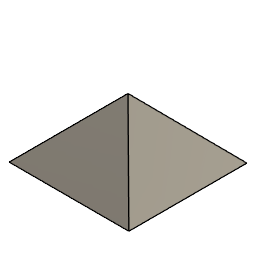
spike (Autodesk Fusion 360 design; units mm, degrees)
part number: 2025-10-12-19-42-02-121
Autodesk Fusion 360 part; units mm, degrees
sketch "base" plane through (0, 0, 0) normal (0, 0, 1) x (1, 0, 0)
  line L0 (25.4, -25.0465) -> (-25.4, -25.0465)
  line L1 (-25.4, -25.0465) -> (-25.4, 25.0465)
  line L2 (-25.4, 25.0465) -> (25.4, 25.0465)
  line L3 (25.4, 25.0465) -> (25.4, -25.0465)
  line L4 (25.4, -25.0465) -> (-25.4, 25.0465) construction
  line L5 (-25.4, -25.0465) -> (25.4, 25.0465) construction
  dimension "d18" = 50.8
  dimension "d19" = 50.093
  constraint horizontal L0
  constraint perpendicular L0 L1
  constraint parallel L0 L2
  constraint parallel L1 L3
  constraint coincident L4 origin
  constraint coincident L5 origin
  measures "d18" distance of L1.end L2.end
  measures "d19" distance of L0.end L1.end
ref_plane "WorkPlane3" through (0, 0, 25.4) normal (0, 0, 1) x (1, 0, 0)
sketch "Sketch6" plane through (0, 0, 25.4) normal (0, 0, 1) x (1, 0, 0)
loft "Loft2" add profiles "base" section 1 section 2 point at (0, 0, 25.4)
